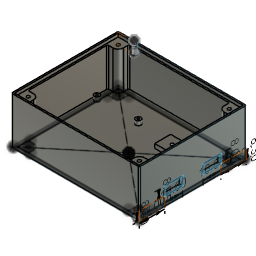
Temperature_Probe-2x-Alerter-Bottom v9 (Autodesk Fusion 360 design; units mm, degrees)
Autodesk Fusion 360 part; units mm, degrees
sketch "Sketch1" plane through (0, 0, 0) normal (0, 0, 1) x (1, 0, 0)
  line L0 (-46.5, 47.5) -> (46.5, 47.5)
  line L1 (57.5, 36.5) -> (57.5, -36.5)
  line L2 (57.5, -47.5) -> (56, -47.5)
  line L3 (-57.5, -36.5) -> (-57.5, 36.5)
  line L4 (-57.5, 47.5) -> (57.5, -47.5) construction
  line L5 (57.5, 47.5) -> (-57.5, -47.5) construction
  line L6 (59.5, -50.5) -> (-59.5, -50.5)
  line L7 (-60.5, -49.5) -> (-60.5, 49.5)
  line L8 (-59.5, 50.5) -> (59.5, 50.5)
  line L9 (60.5, 49.5) -> (60.5, -49.5)
  line L10 (60.5, -50.5) -> (-60.5, 50.5) construction
  line L11 (-60.5, -50.5) -> (60.5, 50.5) construction
  line L12 (-57.5, 47.5) -> (-47.5, 47.5)
  line L13 (-47.5, 46.5) -> (-47.5, 42.5)
  line L14 (-52.5, 37.5) -> (-56.5, 37.5)
  line L15 (-57.5, 37.5) -> (-57.5, 47.5)
  line L16 (57.5, 47.5) -> (47.5, 47.5)
  line L17 (47.5, 46.5) -> (47.5, 42.5)
  line L18 (52.5, 37.5) -> (56.5, 37.5)
  line L19 (57.5, 37.5) -> (57.5, 47.5)
  line L20 (-57.5, -47.5) -> (-47.5, -47.5)
  line L21 (-47.5, -46.5) -> (-47.5, -42.5)
  line L22 (-52.5, -37.5) -> (-56.5, -37.5)
  line L23 (-57.5, -37.5) -> (-57.5, -47.5)
  line L24 (57.5, -47.5) -> (47.5, -47.5)
  line L25 (47.5, -46.5) -> (47.5, -42.5)
  line L26 (52.5, -37.5) -> (56.5, -37.5)
  line L27 (57.5, -37.5) -> (57.5, -47.5)
  line L28 (-57.5, 47.5) -> (-52.5, 47.5) construction
  line L29 (-52.5, 47.5) -> (-52.5, 42.5) construction
  line L30 (-52.5, 42.5) -> (-57.5, 42.5) construction
  line L31 (-57.5, 42.5) -> (-57.5, 47.5) construction
  line L32 (57.5, 47.5) -> (52.5, 47.5) construction
  line L33 (52.5, 47.5) -> (52.5, 42.5) construction
  line L34 (52.5, 42.5) -> (57.5, 42.5) construction
  line L35 (57.5, 42.5) -> (57.5, 47.5) construction
  line L36 (-57.5, -47.5) -> (-52.5, -47.5) construction
  line L37 (-52.5, -47.5) -> (-52.5, -42.5) construction
  line L38 (-52.5, -42.5) -> (-57.5, -42.5) construction
  line L39 (-57.5, -42.5) -> (-57.5, -47.5) construction
  line L40 (57.5, -47.5) -> (52.5, -47.5) construction
  line L41 (52.5, -47.5) -> (52.5, -42.5) construction
  line L42 (52.5, -42.5) -> (57.5, -42.5) construction
  line L43 (57.5, -42.5) -> (57.5, -47.5) construction
  circle A0 centre (-52.5, 42.5) radius 1.5
  circle A1 centre (52.5, 42.5) radius 1.5
  circle A2 centre (-52.5, -42.5) radius 1.5
  circle A3 centre (52.5, -42.5) radius 1.5
  arc A4 (52.5, -37.5) -> (47.5, -42.5) centre (52.5, -42.5) ccw
  arc A5 (-47.5, -42.5) -> (-52.5, -37.5) centre (-52.5, -42.5) ccw
  arc A6 (-52.5, 37.5) -> (-47.5, 42.5) centre (-52.5, 42.5) ccw
  arc A7 (47.5, 42.5) -> (52.5, 37.5) centre (52.5, 42.5) ccw
  arc A8 (-46.5, 47.5) -> (-47.5, 46.5) centre (-46.5, 46.5) ccw
  arc A9 (-56.5, 37.5) -> (-57.5, 36.5) centre (-56.5, 36.5) ccw
  arc A10 (47.5, 46.5) -> (46.5, 47.5) centre (46.5, 46.5) ccw
  arc A11 (57.5, 36.5) -> (56.5, 37.5) centre (56.5, 36.5) ccw
  arc A12 (-57.5, -36.5) -> (-56.5, -37.5) centre (-56.5, -36.5) ccw
  arc A13 (-47.5, -46.5) -> (-46.5, -47.5) centre (-46.5, -46.5) ccw
  arc A14 (56.5, -37.5) -> (57.5, -36.5) centre (56.5, -36.5) ccw
  line L44 (57.5, 47.5) -> (-57.5, 47.5)
  line L45 (-57.5, 47.5) -> (-57.5, -47.5)
  line L46 (-57.5, -47.5) -> (46.5, -47.5)
  line L47 (57.5, -47.5) -> (57.5, 47.5)
  line L48 (57.5, 47.5) -> (-57.5, -47.5) construction
  line L49 (-57.5, 47.5) -> (57.5, -47.5) construction
  line L50 (59, 49) -> (-59, 49)
  line L51 (-59, 49) -> (-59, -49)
  line L52 (-59, -49) -> (59, -49)
  line L53 (59, -49) -> (59, 49)
  line L54 (59, 49) -> (-59, -49) construction
  line L55 (-59, 49) -> (59, -49) construction
  arc A15 (60.5, 49.5) -> (59.5, 50.5) centre (59.5, 49.5) ccw
  arc A16 (59.5, -50.5) -> (60.5, -49.5) centre (59.5, -49.5) ccw
  arc A17 (-60.5, -49.5) -> (-59.5, -50.5) centre (-59.5, -49.5) ccw
  arc A18 (-59.5, 50.5) -> (-60.5, 49.5) centre (-59.5, 49.5) ccw
  arc A19 (46.5, -47.5) -> (47.5, -46.5) centre (46.5, -46.5) ccw
  line L56 (57.5, -47.5) -> (52.5, -47.5)
  line L57 (57.5, -47.5) -> (-57.5, -47.5)
  line L58 (-57.5, -47.5) -> (-57.5, 47.5)
  line L59 (-57.5, 47.5) -> (57.5, 47.5)
  line L60 (57.5, 47.5) -> (57.5, -47.5)
  line L61 (57.5, -47.5) -> (-57.5, 47.5) construction
  line L62 (-57.5, -47.5) -> (57.5, 47.5) construction
  dimension "d5" = 115
  dimension "d6" = 95
  dimension "d7" = 121
  dimension "d8" = 101
  dimension "d13" = 10
  dimension "d14" = 10
  dimension "d15" = 10
  dimension "d16" = 10
  dimension "d17" = 10
  dimension "d18" = 10
  dimension "d19" = 10
  dimension "d20" = 10
  dimension "d21" = 5
  dimension "d22" = 5
  dimension "d23" = 5
  dimension "d24" = 5
  dimension "d25" = 5
  dimension "d26" = 5
  dimension "d27" = 5
  dimension "d28" = 5
  dimension "d29" = 3
  dimension "d30" = 3
  dimension "d31" = 3
  dimension "d32" = 3
  dimension "d33" = 5
  dimension "d34" = 1
  dimension "d35" = 115
  dimension "d36" = 95
  dimension "d38" = 118
  dimension "d39" = 98
  dimension "d41" = 1
  dimension "d42" = 1
  dimension "d43" = 115
  dimension "d44" = 95
  constraint horizontal L0
  constraint perpendicular L0 L1
  constraint parallel L0 L2
  constraint parallel L1 L3
  constraint coincident L4 origin
  constraint coincident L5 origin
  constraint horizontal L6
  constraint perpendicular L6 L7
  constraint parallel L6 L8
  constraint parallel L7 L9
  constraint coincident L10 origin
  constraint coincident L11 origin
  constraint horizontal L12
  constraint vertical L13
  constraint horizontal L14
  constraint vertical L15
  constraint horizontal L16
  constraint vertical L17
  constraint horizontal L18
  constraint vertical L19
  constraint horizontal L20
  constraint vertical L21
  constraint horizontal L22
  constraint vertical L23
  constraint horizontal L24
  constraint vertical L25
  constraint horizontal L26
  constraint vertical L27
  constraint horizontal L28
  constraint vertical L29
  constraint horizontal L30
  constraint vertical L31
  constraint horizontal L32
  constraint vertical L33
  constraint horizontal L34
  constraint vertical L35
  constraint horizontal L36
  constraint vertical L37
  constraint horizontal L38
  constraint vertical L39
  constraint horizontal L40
  constraint vertical L41
  constraint horizontal L42
  constraint vertical L43
  constraint coincident L29.end L30.start
  constraint coincident L33.end L34.start
  constraint coincident L37.end L38.start
  constraint coincident L41.end L42.start
  constraint tangent L25 A4
  constraint tangent L26 A4
  constraint tangent L21 A5
  constraint tangent L22 A5
  constraint equal A4 A5
  constraint tangent L14 A6
  constraint tangent L13 A6
  constraint equal A4 A6
  constraint tangent L17 A7
  constraint tangent L18 A7
  constraint equal A4 A7
  constraint coincident L12.end L13
  constraint coincident L4.start L0
  constraint tangent L13 A8
  constraint tangent L0 A8
  constraint coincident L15.start L14
  constraint coincident L4.start L3
  constraint tangent L14 A9
  constraint tangent L3 A9
  constraint equal A8 A9
  constraint coincident L5.start L0
  constraint coincident L16.end L17
  constraint tangent L0 A10
  constraint tangent L17 A10
  constraint equal A8 A10
  constraint coincident L19.start L18
  constraint coincident L5.start L1
  constraint tangent L18 A11
  constraint tangent L1 A11
  constraint equal A8 A11
  constraint coincident L23.start L22
  constraint coincident L5.end L3
  constraint tangent L22 A12
  constraint tangent L3 A12
  constraint equal A8 A12
  constraint coincident L20.end L21
  constraint coincident L5.end L2
  constraint tangent L21 A13
  constraint tangent L2 A13
  constraint equal A8 A13
  constraint coincident L24.end L25
  constraint coincident L2 A13.end
  constraint coincident L27.start L26
  constraint coincident L2.start L1
  constraint tangent L26 A14
  constraint tangent L1 A14
  constraint equal A8 A14
  constraint horizontal L44
  constraint perpendicular L44 L45
  constraint parallel L44 L46
  constraint parallel L45 L47
  constraint coincident L48 origin
  constraint coincident L49 origin
  constraint horizontal L50
  constraint perpendicular L50 L51
  constraint parallel L50 L52
  constraint parallel L51 L53
  constraint coincident L54 origin
  constraint coincident L55 origin
  constraint coincident L11.end L8
  constraint coincident L11.end L9
  constraint tangent L8 A15
  constraint tangent L9 A15
  constraint coincident L10.start L9
  constraint coincident L10.start L6
  constraint tangent L9 A16
  constraint tangent L6 A16
  constraint equal A15 A16
  constraint coincident L11.start L6
  constraint coincident L11.start L7
  constraint tangent L6 A17
  constraint tangent L7 A17
  constraint equal A15 A17
  constraint coincident L10.end L7
  constraint coincident L10.end L8
  constraint tangent L7 A18
  constraint tangent L8 A18
  constraint equal A15 A18
  constraint coincident L2.start L46
  constraint tangent L25 A19
  constraint tangent L46 A19
  constraint coincident L46 L40.end
  constraint horizontal L57
  constraint perpendicular L57 L58
  constraint parallel L57 L59
  constraint parallel L58 L60
  constraint coincident L61 origin
  constraint coincident L62 origin
  measures "d5" distance of L2.start L5.end
  measures "d6" distance of L5.start L2.start
  measures "d7" distance of L10.end L11.end
  measures "d8" distance of L11.start L10.end
  measures "d13" distance of L4.start L12.end
  measures "d14" distance of L4.start L15.start
  measures "d15" distance of L5.start L16.end
  measures "d16" distance of L5.start L19.start
  measures "d17" distance of L5.end L20.end
  measures "d18" distance of L5.end L23.start
  measures "d19" distance of L2.start L24.end
  measures "d20" distance of L2.start L27.start
  measures "d21" distance of L4.start L28.end
  measures "d22" distance of L4.start L30.end
  measures "d23" distance of L5.start L32.end
  measures "d24" distance of L5.start L34.end
  measures "d25" distance of L5.end L36.end
  measures "d26" distance of L5.end L38.end
  measures "d27" distance of L2.start L40.end
  measures "d28" distance of L2.start L42.end
  measures "d29" diameter of A0
  measures "d30" diameter of A1 A13.centre
  measures "d31" diameter of A2
  measures "d32" diameter of A3 origin
  measures "d33" radius of A4
  measures "d34" radius of A8
  measures "d35" distance of L5.end L2.start
  measures "d36" distance of L4.start L5.end
  measures "d38" distance of L51.end L52.end
  measures "d39" distance of L50.end L51.end
  measures "d41" radius of A15
  measures "d42" radius of A19
  measures "d43" distance of L4.start L5.start
  measures "d44" distance of L5.end L4.start
extrude "Extrude1" add sketch "Sketch1" along normal blind 5 contours L0 L1 L3 L13 L14 L17 L18 L21 L22 L25 L26 A4 A5 A6 A7 A8 A9 A10 A11 A12 A13 A14 L44 L45 L46 L47 A19 L57 L58 L59 L60
extrude "Extrude2" add sketch "Sketch1" along normal blind 41 contours L12 L13 L14 L15 A6 A8 A9 L44 L45 L58 L59 | L16 L17 L18 L19 A7 A10 A11 L44 L47 L59 L60 | L20 L21 L22 L23 A5 A12 A13 L45 L46 L57 L58 | L2 L24 L25 L26 L27 A4 A14 L47 A19 L56 L57 L60 | L50 L51 L52 L53
extrude "Extrude3" add sketch "Sketch1" along normal blind 44 contours L6 L7 L8 L9 A15 A16 A17 A18
extrude "Extrude4" add sketch "Sketch1" along normal blind 12 contours A0 | A1 | A2 | A3
sketch "Sketch2" plane through (60.5, 0, 0) normal (1, 0, 0) x (0, 1, 0)
  line L0 (-49.5, 0) -> (49.5, 0)
  line L1 (49.5, 0) -> (49.5, 44)
  line L2 (49.5, 44) -> (-49.5, 44)
  line L3 (-49.5, 44) -> (-49.5, 0)
  line L4 (-50.5, 0) -> (-26.5, 0) construction
  line L5 (-26.5, 0) -> (-26.5, 8.3) construction
  line L6 (-26.5, 8.3) -> (-50.5, 8.3) construction
  line L7 (-50.5, 8.3) -> (-50.5, 0) construction
  line L8 (50.5, 0) -> (26.5, 0) construction
  line L9 (26.5, 0) -> (26.5, 8.3) construction
  line L10 (26.5, 8.3) -> (50.5, 8.3) construction
  line L11 (50.5, 8.3) -> (50.5, 0) construction
  line L12 (-26.5, 8.3) -> (-9.7, 8.3)
  line L13 (-9.7, 8.3) -> (-9.7, 16.35)
  line L14 (-9.7, 16.35) -> (-26.5, 16.35)
  line L15 (-26.5, 16.35) -> (-26.5, 8.3)
  line L16 (26.5, 8.3) -> (9.7, 8.3)
  line L17 (9.7, 8.3) -> (9.7, 16.35)
  line L18 (9.7, 16.35) -> (26.5, 16.35)
  line L19 (26.5, 16.35) -> (26.5, 8.3)
  dimension "d58" = 24
  dimension "d59" = 8.3
  dimension "d60" = 24
  dimension "d61" = 8.3
  dimension "d62" = 16.8
  dimension "d63" = 8.05
  dimension "d64" = 16.8
  dimension "d65" = 8.05
  constraint horizontal L4
  constraint vertical L5
  constraint horizontal L6
  constraint vertical L7
  constraint horizontal L8
  constraint vertical L9
  constraint horizontal L10
  constraint vertical L11
  constraint horizontal L12
  constraint vertical L13
  constraint horizontal L14
  constraint vertical L15
  constraint horizontal L16
  constraint vertical L17
  constraint horizontal L18
  constraint vertical L19
  measures "d58" distance of L4.start L4.end
  measures "d59" distance of L4.start L6.end
  measures "d60" distance of L8.start L8.end
  measures "d61" distance of L8.start L10.end
  measures "d62" distance of L5.end L12.end
  measures "d63" distance of L5.end L14.end
  measures "d64" distance of L9.end L16.end
  measures "d65" distance of L9.end L18.end
extrude "Extrude5" cut sketch "Sketch2" against normal blind 6 contours L12 L13 L14 L15 | L16 L17 L18 L19
sketch "Sketch3" plane through (0, 50.5, 0) normal (0, 1, 0) x (-1, 0, 0)
  line L0 (-59.5, 0) -> (59.5, 0)
  line L1 (59.5, 0) -> (59.5, 44)
  line L2 (59.5, 44) -> (-59.5, 44)
  line L3 (-59.5, 44) -> (-59.5, 0)
  line L4 (60.5, 44, -1) -> (45.5, 44, -1) construction
  line L5 (45.5, 44, -1) -> (45.5, 34, -1) construction
  line L6 (45.5, 34, -1) -> (60.5, 34, -1) construction
  line L7 (60.5, 34, -1) -> (60.5, 44, -1) construction
  line L8 (45.5, 44) -> (42.3, 44)
  line L9 (42.3, 44) -> (42.3, 35.5)
  line L10 (43.8, 34) -> (44, 34)
  line L11 (45.5, 35.5) -> (45.5, 44)
  arc A0 (42.3, 35.5) -> (43.8, 34) centre (43.8, 35.5) ccw
  arc A1 (44, 34) -> (45.5, 35.5) centre (44, 35.5) ccw
  point P0 (45.5, 34)
  dimension "d68" = 15
  dimension "d69" = 10
  dimension "d70" = 3.2
  dimension "d71" = 10
  dimension "d72" = 1.5
  constraint horizontal L8
  constraint vertical L9
  constraint horizontal L10
  constraint vertical L11
  constraint coincident L2 L8.start
  constraint tangent L9 A0
  constraint tangent L10 A0
  constraint coincident P0 L10
  constraint coincident P0 L11
  constraint tangent L10 A1
  constraint tangent L11 A1
  constraint equal A0 A1
  measures "d70" distance of L8.start L8.end
  measures "d71" distance of L8.start P0
  measures "d72" radius of A0
extrude "Extrude6" cut sketch "Sketch3" against normal blind 6 contours L2 L8 L9 L10 L11 A0 A1
sketch "Sketch4" plane through (0, 0, 5) normal (0, 0, 1) x (-1, 0, 0)
  line L0 (-52.5, 37.5) -> (-56.5, 37.5)
  arc A0 (-56.5, 37.5) -> (-57.5, 36.5) centre (-56.5, 36.5) ccw
  line L1 (-57.5, 36.5) -> (-57.5, -36.5)
  arc A1 (-57.5, -36.5) -> (-56.5, -37.5) centre (-56.5, -36.5) ccw
  line L2 (-56.5, -37.5) -> (-52.5, -37.5)
  arc A2 (-47.5, -42.5) -> (-52.5, -37.5) centre (-52.5, -42.5) ccw
  line L3 (-47.5, -42.5) -> (-47.5, -46.5)
  arc A3 (-47.5, -46.5) -> (-46.5, -47.5) centre (-46.5, -46.5) ccw
  line L4 (-46.5, -47.5) -> (46.5, -47.5)
  arc A4 (46.5, -47.5) -> (47.5, -46.5) centre (46.5, -46.5) ccw
  line L5 (47.5, -46.5) -> (47.5, -42.5)
  arc A5 (52.5, -37.5) -> (47.5, -42.5) centre (52.5, -42.5) ccw
  line L6 (52.5, -37.5) -> (56.5, -37.5)
  arc A6 (56.5, -37.5) -> (57.5, -36.5) centre (56.5, -36.5) ccw
  line L7 (57.5, -36.5) -> (57.5, 36.5)
  arc A7 (57.5, 36.5) -> (56.5, 37.5) centre (56.5, 36.5) ccw
  line L8 (56.5, 37.5) -> (52.5, 37.5)
  arc A8 (47.5, 42.5) -> (52.5, 37.5) centre (52.5, 42.5) ccw
  line L9 (47.5, 42.5) -> (47.5, 46.5)
  arc A9 (47.5, 46.5) -> (46.5, 47.5) centre (46.5, 46.5) ccw
  line L10 (46.5, 47.5) -> (-46.5, 47.5)
  arc A10 (-46.5, 47.5) -> (-47.5, 46.5) centre (-46.5, 46.5) ccw
  line L11 (-47.5, 46.5) -> (-47.5, 42.5)
  arc A11 (-52.5, 37.5) -> (-47.5, 42.5) centre (-52.5, 42.5) ccw
  line L12 (-60.6157, 50.6722) -> (-41.1157, 50.6722) construction
  line L13 (-41.1157, 50.6722) -> (-41.1157, 26.6722) construction
  line L14 (-41.1157, 26.6722) -> (-60.6157, 26.6722) construction
  line L15 (-60.6157, 26.6722) -> (-60.6157, 50.6722) construction
  line L16 (-60.5, -50.5) -> (-41, -50.5) construction
  line L17 (-41, -50.5) -> (-41, -26.5) construction
  line L18 (-41, -26.5) -> (-60.5, -26.5) construction
  line L19 (-60.5, -26.5) -> (-60.5, -50.5) construction
  line L20 (57.5, -35) -> (57.5, 35.0916) construction
  line L21 (60.5, 50.5) -> (53.5, 50.5) construction
  line L22 (53.5, 50.5) -> (53.5, 30.5) construction
  line L23 (53.5, 30.5) -> (60.5, 30.5) construction
  line L24 (60.5, 30.5) -> (60.5, 50.5) construction
  circle A12 centre (53.5, 30.5) radius 1
  circle A13 centre (53.5, 30.5) radius 2.5
  line L25 (53.5, 30.5) -> (14.5, 30.5) construction
  line L26 (14.5, 30.5) -> (14.5, -23.5) construction
  line L27 (14.5, -23.5) -> (53.5, -23.5) construction
  line L28 (53.5, -23.5) -> (53.5, 30.5) construction
  circle A14 centre (53.5, -23.5) radius 1
  circle A15 centre (53.5, -23.5) radius 2.5
  circle A16 centre (14.5, -23.5) radius 1
  circle A17 centre (14.5, -23.5) radius 2.5
  circle A18 centre (14.5, 30.5) radius 1
  circle A19 centre (14.5, 30.5) radius 2.5
  dimension "d75" = 19.5
  dimension "d76" = 24
  dimension "d77" = 19.5
  dimension "d78" = 24
  dimension "d113" = 7
  dimension "d114" = 20
  dimension "d115" = 2
  dimension "d116" = 5
  dimension "d117" = 39
  dimension "d118" = 54
  dimension "d119" = 2
  dimension "d120" = 5
  dimension "d121" = 2
  dimension "d122" = 5
  dimension "d123" = 2
  dimension "d124" = 5
  constraint horizontal L12
  constraint vertical L13
  constraint horizontal L14
  constraint vertical L15
  constraint horizontal L16
  constraint vertical L17
  constraint horizontal L18
  constraint vertical L19
  constraint vertical L20
  constraint coincident L7 L20.end
  constraint horizontal L21
  constraint vertical L22
  constraint horizontal L23
  constraint vertical L24
  constraint coincident L22.end L23.start
  constraint concentric A12 A13
  constraint horizontal L25
  constraint vertical L26
  constraint horizontal L27
  constraint vertical L28
  constraint coincident L27.end L28.start
  constraint concentric A14 A15
  constraint coincident L26.end L27.start
  constraint concentric A16 A17
  constraint coincident L25.end L26.start
  constraint concentric A18 A19
  measures "d75" distance of L12.start L12.end
  measures "d76" distance of L12.start L14.end
  measures "d77" distance of L16.start L16.end
  measures "d78" distance of L16.start L18.end
  measures "d113" distance of L21.start L21.end
  measures "d114" distance of L21.start L23.end
  measures "d115" diameter of A12
  measures "d116" diameter of A13
  measures "d117" distance of L22.end L25.end
  measures "d118" distance of L22.end L27.end
  measures "d119" diameter of A14
  measures "d120" diameter of A15
  measures "d121" diameter of A16
  measures "d122" diameter of A17
  measures "d123" diameter of A18
  measures "d124" diameter of A19
sketch "Sketch5" plane through (0, 0, 5) normal (0, 0, 1) x (-1, 0, 0)
  line L0 (-57.476, 47.531) -> (-22.476, 47.531) construction
  line L1 (-22.476, 47.531) -> (-22.476, 17.531) construction
  line L2 (-22.476, 17.531) -> (-57.476, 17.531) construction
  line L3 (-57.476, 17.531) -> (-57.476, 47.531) construction
  line L4 (-57.5, -47.5) -> (-22.5, -47.5) construction
  line L5 (-22.5, -47.5) -> (-22.5, -18.5) construction
  line L6 (-22.5, -18.5) -> (-57.5, -18.5) construction
  line L7 (-57.5, -18.5) -> (-57.5, -47.5) construction
  circle A0 centre (-22.476, 17.531) radius 5
  circle A1 centre (-22.476, 17.531) radius 1.5
  circle A2 centre (-22.5, -18.5) radius 5
  circle A3 centre (-22.5, -18.5) radius 1.5
  line L8 (-22.5, -18.5) -> (-13.5, -18.5) construction
  line L9 (-13.5, -18.5) -> (-13.5, -11) construction
  line L10 (-13.5, -11) -> (-22.5, -11) construction
  line L11 (-22.5, -11) -> (-22.5, -18.5) construction
  line L12 (-13.5, -11) -> (-31.5, -11)
  line L13 (-31.5, -11) -> (-31.5, -26)
  line L14 (-31.5, -26) -> (-13.5, -26)
  line L15 (-13.5, -26) -> (-13.5, -11)
  line L16 (-22.476, 17.531) -> (-13.476, 17.531) construction
  line L17 (-13.476, 17.531) -> (-13.476, 25.031) construction
  line L18 (-13.476, 25.031) -> (-22.476, 25.031) construction
  line L19 (-22.476, 25.031) -> (-22.476, 17.531) construction
  line L20 (-13.476, 25.031) -> (-31.476, 25.031)
  line L21 (-31.476, 25.031) -> (-31.476, 10.031)
  line L22 (-31.476, 10.031) -> (-13.476, 10.031)
  line L23 (-13.476, 10.031) -> (-13.476, 25.031)
  dimension "d97" = 35
  dimension "d98" = 30
  dimension "d99" = 35
  dimension "d100" = 29
  dimension "d101" = 10
  dimension "d102" = 3
  dimension "d103" = 10
  dimension "d104" = 3
  dimension "d125" = 9
  dimension "d126" = 7.5
  dimension "d127" = 18
  dimension "d128" = 15
  dimension "d129" = 9
  dimension "d130" = 7.5
  dimension "d131" = 18
  dimension "d132" = 15
  constraint horizontal L0
  constraint vertical L1
  constraint horizontal L2
  constraint vertical L3
  constraint horizontal L4
  constraint vertical L5
  constraint horizontal L6
  constraint vertical L7
  constraint coincident L1.end L2.start
  constraint concentric A0 A1
  constraint coincident L5.end L6.start
  constraint concentric A2 A3
  constraint horizontal L8
  constraint vertical L9
  constraint horizontal L10
  constraint vertical L11
  constraint horizontal L12
  constraint vertical L13
  constraint horizontal L14
  constraint vertical L15
  constraint horizontal L16
  constraint vertical L17
  constraint horizontal L18
  constraint vertical L19
  constraint horizontal L20
  constraint vertical L21
  constraint horizontal L22
  constraint vertical L23
  measures "d97" distance of L0.start L0.end
  measures "d98" distance of L0.start L2.end
  measures "d99" distance of L4.start L4.end
  measures "d100" distance of L4.start L6.end
  measures "d101" diameter of A0
  measures "d102" diameter of A1
  measures "d103" diameter of A2
  measures "d104" diameter of A3
  measures "d125" distance of L5.end L8.end
  measures "d126" distance of L5.end L10.end
  measures "d127" distance of L9.end L12.end
  measures "d128" distance of L9.end L14.end
  measures "d129" distance of L1.end L16.end
  measures "d130" distance of L1.end L18.end
  measures "d131" distance of L17.end L20.end
  measures "d132" distance of L17.end L22.end
extrude "Extrude9" add sketch "Sketch5" along normal blind 4 contours A0 | A2
extrude "Extrude10" cut 2 faces at (22.8698, -16.8266, 5) (22.8938, 19.2044, 5) along direction (0, 0, -1) blind 2.5
sketch "Sketch6" plane through (0, 0, 5) normal (0, 0, 1) x (1, 0, 0)
extrude "Extrude11" add sketch "Sketch5" along normal blind 4 contours L12 L13 L14 L15 | L20 L21 L22 L23
extrude "Extrude12" add sketch "Sketch4" along normal blind 4 contours A13 | A15 | A17 | A19
extrude "Extrude13" cut 4 faces at (-14.1815, 23.4017, 5) (-14.1815, -30.5983, 5) (-53.1073, -30.2733, 5) (-54.0264, 23.7911, 5) along direction (0, 0, -1) blind 4
equation "Inner_Width = 95 mm"
equation "Inner_Length = 115 mm"
equation "Inner_Height = 36 mm"
equation "Case_Wall_Thickness = 6 mm"
equation "d5 = Inner_Length"
equation "d6 = Inner_Width"
equation "d7 = Inner_Length + Case_Wall_Thickness"
equation "d8 = Inner_Width + Case_Wall_Thickness"
equation "stud_size = 10 mm"
equation "stud_fillet = 5 mm"
equation "stud_filet_corner = 1 mm"
equation "stud_lid_screw_diameter = 3 mm"
equation "d13 = stud_size"
equation "d14 = stud_size"
equation "d15 = stud_size"
equation "d16 = stud_size"
equation "d17 = stud_size"
equation "d18 = stud_size"
equation "d19 = stud_size"
equation "d20 = stud_size"
equation "d21 = stud_size / 2"
equation "d22 = stud_size / 2"
equation "d23 = stud_size / 2"
equation "d24 = stud_size / 2"
equation "d25 = stud_size / 2"
equation "d26 = stud_size / 2"
equation "d27 = stud_size / 2"
equation "d28 = stud_size / 2"
equation "d29 = stud_lid_screw_diameter"
equation "d30 = stud_lid_screw_diameter"
equation "d31 = stud_lid_screw_diameter"
equation "d32 = stud_lid_screw_diameter"
equation "d33 = stud_fillet"
equation "d35 = Inner_Length"
equation "d36 = Inner_Width"
equation "Case_Wall_Thickness_Middle = 3 mm"
equation "d38 = Inner_Length + Case_Wall_Thickness_Middle"
equation "d39 = Inner_Width + Case_Wall_Thickness_Middle"
equation "outer_box_fil = 1 mm"
equation "d41 = outer_box_fil"
equation "d43 = Inner_Length"
equation "d44 = Inner_Width"
equation "height_inner = 36 mm + bottom_thickness"
equation "height_lid_offset = 3 mm"
equation "height_outer = height_inner + height_lid_offset"
equation "bottom_thickness = 5 mm"
equation "d49 = bottom_thickness"
equation "d51 = height_inner"
equation "d53 = height_outer"
equation "lid_screw_depth = 24 mm"
equation "d56 = Inner_Height - lid_screw_depth"
equation "d66 = -Case_Wall_Thickness"
equation "d73 = -Case_Wall_Thickness"
